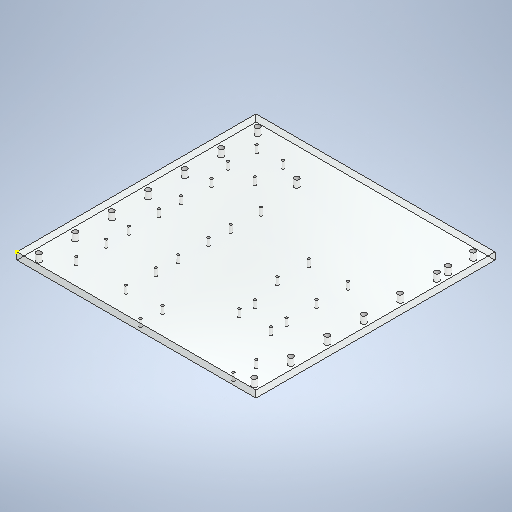
# Autodesk Inventor part: acrylic_base_2
Saved by Autodesk Inventor 2025.1 (Build 291241000, 241)
## iProperties
Created: 2026-09-08
Part Number: acrylic_base_2
Material: Generic
Document SubType Name: Modeling
Designer: Aiden
Density: 1 g/cm^3
Appearance: Default
Author: Aiden
Autodesk Inventor part; units mm, degrees
ref_plane "YZ Plane" through (0, 0, 0) normal (1, 0, 0) x (0, 1, 0)
ref_plane "XZ Plane" through (0, 0, 0) normal (0, 1, 0) x (-1, 0, 0)
ref_plane "XY Plane" through (0, 0, 0) normal (0, 0, 1) x (1, 0, 0)
sketch "Sketch1" plane through (0, 0, 0) normal (0, 1, 0) x (-1, 0, 0)
  line L0 (0, 0) -> (-304.8, 0)
  line L1 (-304.8, 0) -> (-304.8, -304.8)
  line L2 (-304.8, -304.8) -> (0, -304.8)
  line L3 (0, -304.8) -> (0, 0)
  dimension "d0" = 304.8
  dimension "d1" = 304.8
  constraints: 8 end point, 2 parallel, 1 horizontal, 1 perpendicular
  measures "d0" distance of L1.end L2.end
  measures "d1" distance of L2.end L0.start
extrude "Extrusion1" add sketch "Sketch1" along normal blind 9
sketch "Sketch3" plane through (0, 9, 0) normal (0, 1, 0) x (1, 0, 0)
  line L0 (304.8, 304.8) -> (0, 304.8) projected
  line L1 (152.4, 304.8) -> (152.4, 0) construction
  line L2 (0, 0) -> (304.8, 0) projected
  line L3 (0, 304.8) -> (0, 0) projected
  line L4 (0, 152.4) -> (304.8, 152.4) construction
  line L5 (304.8, 0) -> (304.8, 304.8) projected
  line L6 (289.8, 259.8) -> (96.8, 259.8) construction
  point P0 (289.8, 152.4)
  point P1 (289.8, 198.9)
  point P2 (289.8, 105.9)
  point P3 (289.8, 245.4)
  point P4 (289.8, 59.4)
  point P5 (289.8, 291.9)
  point P6 (289.8, 12.9)
  point P7 (15, 152.4)
  point P8 (15, 198.9)
  point P9 (15, 105.9)
  point P10 (15, 245.4)
  point P11 (15, 59.4)
  point P12 (15, 291.9)
  point P13 (15, 12.9)
  dimension "d20" = 193
  dimension "d38" = 46.5
  dimension "d43" = 45
  dimension "d44" = 15
  dimension "d45" = 15
  dimension "d46" = 12.9
  constraints: 7 symmetric about line, 6 end point, 4 midpoint, 1 coincident, 1 horizontal, 1 vertical, 6 other
  measures "d20" distance of L6.start L6.end
  measures "d38" distance of point (289.8, 152.4) point (289.8, 198.9)
  measures "d43" distance from line of L0 L6.start
  measures "d44" distance from line of L6.start L5
  measures "d45" distance from line of L5 point (289.8, 152.4)
  measures "d46" distance from line of point (289.8, 291.9) L0
hole "Hole1" at (289.8, 9, -152.4) at (96.8, 9, -259.8) at (289.8, 9, -259.8) at (15, 9, -291.9) at (15, 9, -245.4) at (15, 9, -198.9) at (15, 9, -152.4) at (15, 9, -105.9) at (15, 9, -59.4) at (15, 9, -12.9) at (289.8, 9, -291.9) at (289.8, 9, -245.4) at (289.8, 9, -105.9) at (289.8, 9, -59.4) at (289.8, 9, -12.9) at (289.8, 9, -198.9) direction (0, -1, 0) diameter 6.6 end through all
sketch "Sketch6" plane through (0, 9, 0) normal (0, 1, 0) x (1, 0, 0)
  point P0 (0, 0)
sketch "Sketch7" plane through (0, 9, 0) normal (0, 1, 0) x (1, 0, 0)
  arc A0 (105.2833, 206.7953) -> (105.2833, 203.5953) centre (105.2833, 205.1953) ccw projected
  line L0 (105.2833, 206.7953) -> (106.5833, 206.7953) projected
  arc A1 (106.5833, 203.5953) -> (106.5833, 206.7953) centre (106.5833, 205.1953) ccw projected
  line L1 (106.5833, 203.5953) -> (105.2833, 203.5953) projected
  arc A2 (106.5833, 165.1391) -> (106.5833, 168.3391) centre (106.5833, 166.7391) ccw projected
  line L2 (106.5833, 165.1391) -> (105.2833, 165.1391) projected
  arc A3 (105.2833, 168.3391) -> (105.2833, 165.1391) centre (105.2833, 166.7391) ccw projected
  line L3 (105.2833, 168.3391) -> (106.5833, 168.3391) projected
  arc A4 (43.3997, 165.1391) -> (43.3997, 168.3391) centre (43.3997, 166.7391) ccw projected
  line L4 (43.3997, 165.1391) -> (42.0997, 165.1391) projected
  arc A5 (42.0997, 168.3391) -> (42.0997, 165.1391) centre (42.0997, 166.7391) ccw projected
  line L5 (42.0997, 168.3391) -> (43.3997, 168.3391) projected
  line L6 (42.0997, 206.7953) -> (43.3997, 206.7953) projected
  arc A6 (43.3997, 203.5953) -> (43.3997, 206.7953) centre (43.3997, 205.1953) ccw projected
  line L7 (43.3997, 203.5953) -> (42.0997, 203.5953) projected
  arc A7 (42.0997, 206.7953) -> (42.0997, 203.5953) centre (42.0997, 205.1953) ccw projected
  spline S0 degree 3 poles (143.1833, 208.4353) (143.1833, 207.0944) (142.4879, 205.7761) (141.3875, 204.9942) (140.2562, 204.1904) (138.7283, 203.9647) (137.4066, 204.3999) (136.1385, 204.8174) (135.0844, 205.8385) (134.6567, 207.0914) (134.2262, 208.3527) (134.4508, 209.8128) (135.2354, 210.8939) (136.0421, 212.0056) (137.4107, 212.691) (138.7942, 212.6953) (138.7989, 212.6953) (138.8036, 212.6953) (138.8083, 212.6953) knots -3.141593 -3.141593 -3.141593 -3.141593 -2.205037 -2.205037 -2.205037 -1.242265 -1.242265 -1.242265 -0.318503 -0.318503 -0.318503 0.611382 0.611382 0.611382 1.567549 1.567549 1.567549 1.570796 1.570796 1.570796 1.570796 projected
  line L8 (9.8747, 212.6953) -> (138.8083, 212.6953) projected
  spline S1 degree 3 poles (9.8747, 212.6953) (11.2253, 212.6951) (12.5648, 212.0482) (13.3808, 210.9836) (13.938, 210.2568) (14.2497, 209.3479) (14.2497, 208.4353) knots 1.570796 1.570796 1.570796 1.570796 2.504243 2.504243 2.504243 3.141593 3.141593 3.141593 3.141593 projected
  spline S2 degree 3 poles (14.2497, 208.4353) (14.2497, 207.0944) (13.5543, 205.7761) (12.4539, 204.9942) (11.3226, 204.1904) (9.7947, 203.9647) (8.473, 204.3999) (7.2049, 204.8174) (6.1508, 205.8385) (5.7231, 207.0914) (5.5756, 207.5234) (5.505, 207.9788) (5.4997, 208.4353) knots -3.141593 -3.141593 -3.141593 -3.141593 -2.205037 -2.205037 -2.205037 -1.242265 -1.242265 -1.242265 -0.318503 -0.318503 -0.318503 0 0 0 0 projected
  line L9 (5.4997, 163.4991) -> (5.4997, 208.4353) projected
  spline S3 degree 3 poles (5.4997, 163.4991) (5.5121, 164.3722) (5.7859, 165.2469) (6.3018, 165.9577) (7.1085, 167.0694) (8.4771, 167.7548) (9.8606, 167.7591) (11.216, 167.7634) (12.5619, 167.1156) (13.3808, 166.0474) (13.938, 165.3206) (14.2497, 164.4117) (14.2497, 163.4991) knots 0 0 0 0 0.611382 0.611382 0.611382 1.567549 1.567549 1.567549 2.504243 2.504243 2.504243 3.141593 3.141593 3.141593 3.141593 projected
  spline S4 degree 3 poles (14.2497, 163.4991) (14.2497, 162.1582) (13.5543, 160.8399) (12.4539, 160.058) (11.7086, 159.5284) (10.7913, 159.2498) (9.8747, 159.2391) knots -3.141593 -3.141593 -3.141593 -3.141593 -2.205037 -2.205037 -2.205037 -1.570796 -1.570796 -1.570796 -1.570796 projected
  line L10 (138.8083, 159.2391) -> (9.8747, 159.2391) projected
  spline S5 degree 3 poles (138.8083, 159.2391) (138.3327, 159.2436) (137.8576, 159.3151) (137.4066, 159.4636) (136.1385, 159.8812) (135.0844, 160.9023) (134.6567, 162.1552) (134.2262, 163.4164) (134.4508, 164.8766) (135.2354, 165.9577) (136.0421, 167.0694) (137.4107, 167.7548) (138.7942, 167.7591) (140.1496, 167.7634) (141.4955, 167.1156) (142.3144, 166.0474) (142.8716, 165.3206) (143.1833, 164.4117) (143.1833, 163.4991) knots -1.570796 -1.570796 -1.570796 -1.570796 -1.242265 -1.242265 -1.242265 -0.318503 -0.318503 -0.318503 0.611382 0.611382 0.611382 1.567549 1.567549 1.567549 2.504243 2.504243 2.504243 3.141593 3.141593 3.141593 3.141593 projected
  line L11 (143.1833, 208.4353) -> (143.1833, 163.4991) projected
  arc A8 (105.2833, 139.7953) -> (105.2833, 136.5953) centre (105.2833, 138.1953) ccw projected
  line L12 (105.2833, 139.7953) -> (106.5833, 139.7953) projected
  arc A9 (106.5833, 136.5953) -> (106.5833, 139.7953) centre (106.5833, 138.1953) ccw projected
  line L13 (106.5833, 136.5953) -> (105.2833, 136.5953) projected
  arc A10 (106.5833, 98.1391) -> (106.5833, 101.3391) centre (106.5833, 99.7391) ccw projected
  line L14 (106.5833, 98.1391) -> (105.2833, 98.1391) projected
  arc A11 (105.2833, 101.3391) -> (105.2833, 98.1391) centre (105.2833, 99.7391) ccw projected
  line L15 (105.2833, 101.3391) -> (106.5833, 101.3391) projected
  arc A12 (43.3997, 98.1391) -> (43.3997, 101.3391) centre (43.3997, 99.7391) ccw projected
  line L16 (43.3997, 98.1391) -> (42.0997, 98.1391) projected
  arc A13 (42.0997, 101.3391) -> (42.0997, 98.1391) centre (42.0997, 99.7391) ccw projected
  line L17 (42.0997, 101.3391) -> (43.3997, 101.3391) projected
  line L18 (42.0997, 139.7953) -> (43.3997, 139.7953) projected
  arc A14 (43.3997, 136.5953) -> (43.3997, 139.7953) centre (43.3997, 138.1953) ccw projected
  line L19 (43.3997, 136.5953) -> (42.0997, 136.5953) projected
  arc A15 (42.0997, 139.7953) -> (42.0997, 136.5953) centre (42.0997, 138.1953) ccw projected
  spline S6 degree 3 poles (143.1833, 141.4353) (143.1833, 140.0944) (142.4879, 138.7761) (141.3875, 137.9942) (140.2562, 137.1904) (138.7283, 136.9647) (137.4066, 137.3999) (136.1385, 137.8174) (135.0844, 138.8385) (134.6567, 140.0914) (134.2262, 141.3527) (134.4508, 142.8128) (135.2354, 143.8939) (136.0421, 145.0056) (137.4107, 145.691) (138.7942, 145.6953) (138.7989, 145.6953) (138.8036, 145.6953) (138.8083, 145.6953) knots -3.141593 -3.141593 -3.141593 -3.141593 -2.205037 -2.205037 -2.205037 -1.242265 -1.242265 -1.242265 -0.318503 -0.318503 -0.318503 0.611382 0.611382 0.611382 1.567549 1.567549 1.567549 1.570796 1.570796 1.570796 1.570796 projected
  line L20 (9.8747, 145.6953) -> (138.8083, 145.6953) projected
  spline S7 degree 3 poles (9.8747, 145.6953) (11.2253, 145.6951) (12.5648, 145.0482) (13.3808, 143.9836) (13.938, 143.2568) (14.2497, 142.3479) (14.2497, 141.4353) knots 1.570796 1.570796 1.570796 1.570796 2.504243 2.504243 2.504243 3.141593 3.141593 3.141593 3.141593 projected
  spline S8 degree 3 poles (14.2497, 141.4353) (14.2497, 140.0944) (13.5543, 138.7761) (12.4539, 137.9942) (11.3226, 137.1904) (9.7947, 136.9647) (8.473, 137.3999) (7.2049, 137.8174) (6.1508, 138.8385) (5.7231, 140.0914) (5.5756, 140.5234) (5.505, 140.9788) (5.4997, 141.4353) knots -3.141593 -3.141593 -3.141593 -3.141593 -2.205037 -2.205037 -2.205037 -1.242265 -1.242265 -1.242265 -0.318503 -0.318503 -0.318503 0 0 0 0 projected
  line L21 (5.4997, 96.4991) -> (5.4997, 141.4353) projected
  spline S9 degree 3 poles (5.4997, 96.4991) (5.5121, 97.3722) (5.7859, 98.2469) (6.3018, 98.9577) (7.1085, 100.0694) (8.4771, 100.7548) (9.8606, 100.7591) (11.216, 100.7634) (12.5619, 100.1156) (13.3808, 99.0474) (13.938, 98.3206) (14.2497, 97.4117) (14.2497, 96.4991) knots 0 0 0 0 0.611382 0.611382 0.611382 1.567549 1.567549 1.567549 2.504243 2.504243 2.504243 3.141593 3.141593 3.141593 3.141593 projected
  spline S10 degree 3 poles (14.2497, 96.4991) (14.2497, 95.1582) (13.5543, 93.8399) (12.4539, 93.058) (11.7086, 92.5284) (10.7913, 92.2498) (9.8747, 92.2391) knots -3.141593 -3.141593 -3.141593 -3.141593 -2.205037 -2.205037 -2.205037 -1.570796 -1.570796 -1.570796 -1.570796 projected
  line L22 (138.8083, 92.2391) -> (9.8747, 92.2391) projected
  spline S11 degree 3 poles (138.8083, 92.2391) (138.3327, 92.2436) (137.8576, 92.3151) (137.4066, 92.4636) (136.1385, 92.8812) (135.0844, 93.9023) (134.6567, 95.1552) (134.2262, 96.4164) (134.4508, 97.8766) (135.2354, 98.9577) (136.0421, 100.0694) (137.4107, 100.7548) (138.7942, 100.7591) (140.1496, 100.7634) (141.4955, 100.1156) (142.3144, 99.0474) (142.8716, 98.3206) (143.1833, 97.4117) (143.1833, 96.4991) knots -1.570796 -1.570796 -1.570796 -1.570796 -1.242265 -1.242265 -1.242265 -0.318503 -0.318503 -0.318503 0.611382 0.611382 0.611382 1.567549 1.567549 1.567549 2.504243 2.504243 2.504243 3.141593 3.141593 3.141593 3.141593 projected
  line L23 (143.1833, 141.4353) -> (143.1833, 96.4991) projected
  arc A16 (105.2833, 72.7953) -> (105.2833, 69.5953) centre (105.2833, 71.1953) ccw projected
  line L24 (105.2833, 72.7953) -> (106.5833, 72.7953) projected
  arc A17 (106.5833, 69.5953) -> (106.5833, 72.7953) centre (106.5833, 71.1953) ccw projected
  line L25 (106.5833, 69.5953) -> (105.2833, 69.5953) projected
  arc A18 (106.5833, 31.1391) -> (106.5833, 34.3391) centre (106.5833, 32.7391) ccw projected
  line L26 (106.5833, 31.1391) -> (105.2833, 31.1391) projected
  arc A19 (105.2833, 34.3391) -> (105.2833, 31.1391) centre (105.2833, 32.7391) ccw projected
  line L27 (105.2833, 34.3391) -> (106.5833, 34.3391) projected
  arc A20 (43.3997, 31.1391) -> (43.3997, 34.3391) centre (43.3997, 32.7391) ccw projected
  line L28 (43.3997, 31.1391) -> (42.0997, 31.1391) projected
  arc A21 (42.0997, 34.3391) -> (42.0997, 31.1391) centre (42.0997, 32.7391) ccw projected
  line L29 (42.0997, 34.3391) -> (43.3997, 34.3391) projected
  line L30 (42.0997, 72.7953) -> (43.3997, 72.7953) projected
  arc A22 (43.3997, 69.5953) -> (43.3997, 72.7953) centre (43.3997, 71.1953) ccw projected
  line L31 (43.3997, 69.5953) -> (42.0997, 69.5953) projected
  arc A23 (42.0997, 72.7953) -> (42.0997, 69.5953) centre (42.0997, 71.1953) ccw projected
  spline S12 degree 3 poles (143.1833, 74.4353) (143.1833, 73.0944) (142.4879, 71.7761) (141.3875, 70.9942) (140.2562, 70.1904) (138.7283, 69.9647) (137.4066, 70.3999) (136.1385, 70.8174) (135.0844, 71.8385) (134.6567, 73.0914) (134.2262, 74.3527) (134.4508, 75.8128) (135.2354, 76.8939) (136.0421, 78.0056) (137.4107, 78.691) (138.7942, 78.6953) (138.7989, 78.6953) (138.8036, 78.6953) (138.8083, 78.6953) knots -3.141593 -3.141593 -3.141593 -3.141593 -2.205037 -2.205037 -2.205037 -1.242265 -1.242265 -1.242265 -0.318503 -0.318503 -0.318503 0.611382 0.611382 0.611382 1.567549 1.567549 1.567549 1.570796 1.570796 1.570796 1.570796 projected
  line L32 (9.8747, 78.6953) -> (138.8083, 78.6953) projected
  spline S13 degree 3 poles (9.8747, 78.6953) (11.2253, 78.6951) (12.5648, 78.0482) (13.3808, 76.9836) (13.938, 76.2568) (14.2497, 75.3479) (14.2497, 74.4353) knots 1.570796 1.570796 1.570796 1.570796 2.504243 2.504243 2.504243 3.141593 3.141593 3.141593 3.141593 projected
  spline S14 degree 3 poles (14.2497, 74.4353) (14.2497, 73.0944) (13.5543, 71.7761) (12.4539, 70.9942) (11.3226, 70.1904) (9.7947, 69.9647) (8.473, 70.3999) (7.2049, 70.8174) (6.1508, 71.8385) (5.7231, 73.0914) (5.5756, 73.5234) (5.505, 73.9788) (5.4997, 74.4353) knots -3.141593 -3.141593 -3.141593 -3.141593 -2.205037 -2.205037 -2.205037 -1.242265 -1.242265 -1.242265 -0.318503 -0.318503 -0.318503 0 0 0 0 projected
  line L33 (5.4997, 29.4991) -> (5.4997, 74.4353) projected
  spline S15 degree 3 poles (5.4997, 29.4991) (5.5121, 30.3722) (5.7859, 31.2469) (6.3018, 31.9577) (7.1085, 33.0694) (8.4771, 33.7548) (9.8606, 33.7591) (11.216, 33.7634) (12.5619, 33.1156) (13.3808, 32.0474) (13.938, 31.3206) (14.2497, 30.4117) (14.2497, 29.4991) knots 0 0 0 0 0.611382 0.611382 0.611382 1.567549 1.567549 1.567549 2.504243 2.504243 2.504243 3.141593 3.141593 3.141593 3.141593 projected
  spline S16 degree 3 poles (14.2497, 29.4991) (14.2497, 28.1582) (13.5543, 26.8399) (12.4539, 26.058) (11.7086, 25.5284) (10.7913, 25.2498) (9.8747, 25.2391) knots -3.141593 -3.141593 -3.141593 -3.141593 -2.205037 -2.205037 -2.205037 -1.570796 -1.570796 -1.570796 -1.570796 projected
  line L34 (138.8083, 25.2391) -> (9.8747, 25.2391) projected
  spline S17 degree 3 poles (138.8083, 25.2391) (138.3327, 25.2436) (137.8576, 25.3151) (137.4066, 25.4636) (136.1385, 25.8812) (135.0844, 26.9023) (134.6567, 28.1552) (134.2262, 29.4164) (134.4508, 30.8766) (135.2354, 31.9577) (136.0421, 33.0694) (137.4107, 33.7548) (138.7942, 33.7591) (140.1496, 33.7634) (141.4955, 33.1156) (142.3144, 32.0474) (142.8716, 31.3206) (143.1833, 30.4117) (143.1833, 29.4991) knots -1.570796 -1.570796 -1.570796 -1.570796 -1.242265 -1.242265 -1.242265 -0.318503 -0.318503 -0.318503 0.611382 0.611382 0.611382 1.567549 1.567549 1.567549 2.504243 2.504243 2.504243 3.141593 3.141593 3.141593 3.141593 projected
  line L35 (143.1833, 74.4353) -> (143.1833, 29.4991) projected
  line L36 (67.8539, 272.6632) -> (69.1539, 272.6637) projected
  arc A24 (69.1553, 269.4637) -> (69.1539, 272.6637) centre (69.1546, 271.0637) ccw projected
  line L37 (69.1553, 269.4637) -> (67.8553, 269.4632) projected
  arc A25 (67.8539, 272.6632) -> (67.8553, 269.4632) centre (67.8546, 271.0632) ccw projected
  arc A26 (67.87, 236.3632) -> (67.8714, 233.1632) centre (67.8707, 234.7632) ccw projected
  line L38 (67.87, 236.3632) -> (69.17, 236.3637) projected
  arc A27 (69.1714, 233.1637) -> (69.17, 236.3637) centre (69.1707, 234.7637) ccw projected
  line L39 (69.1714, 233.1637) -> (67.8714, 233.1632) projected
  arc A28 (33.8664, 272.6481) -> (33.8678, 269.4481) centre (33.8671, 271.0481) ccw projected
  line L40 (33.8664, 272.6481) -> (35.1664, 272.6486) projected
  arc A29 (35.1678, 269.4486) -> (35.1664, 272.6486) centre (35.1671, 271.0486) ccw projected
  line L41 (35.1678, 269.4486) -> (33.8678, 269.4481) projected
  line L42 (33.8825, 236.3481) -> (35.1825, 236.3486) projected
  arc A30 (35.1839, 233.1486) -> (35.1825, 236.3486) centre (35.1832, 234.7486) ccw projected
  line L43 (35.1839, 233.1486) -> (33.8839, 233.1481) projected
  arc A31 (33.8825, 236.3481) -> (33.8839, 233.1481) centre (33.8832, 234.7481) ccw projected
  arc A32 (17.2653, 275.1407) -> (21.2635, 279.1425) centre (21.2653, 275.1425) ccw projected
  line L44 (17.285, 230.6407) -> (17.2653, 275.1407) projected
  arc A33 (21.2868, 226.6425) -> (17.285, 230.6407) centre (21.285, 230.6425) ccw projected
  line L45 (81.7743, 226.6693) -> (21.2868, 226.6425) projected
  arc A34 (81.7743, 226.6693) -> (85.7725, 230.6711) centre (81.7725, 230.6693) ccw projected
  line L46 (85.7627, 252.9211) -> (85.7725, 230.6711) projected
  circle A35 centre (81.7627, 252.9193) radius 4 projected
  line L47 (85.7528, 275.1711) -> (85.7627, 252.9211) projected
  arc A36 (85.7528, 275.1711) -> (81.751, 279.1693) centre (81.7528, 275.1693) ccw projected
  line L48 (21.2635, 279.1425) -> (81.751, 279.1693) projected
  arc A37 (194.1246, 137.0569) -> (194.1232, 140.2569) centre (194.1239, 138.6569) ccw projected
  line L49 (194.1246, 137.0569) -> (192.8246, 137.0563) projected
  arc A38 (192.8232, 140.2563) -> (192.8246, 137.0563) centre (192.8239, 138.6563) ccw projected
  line L50 (192.8232, 140.2563) -> (194.1232, 140.2569) projected
  line L51 (194.1069, 177.0569) -> (192.8069, 177.0563) projected
  arc A39 (192.8054, 180.2563) -> (192.8069, 177.0563) centre (192.8061, 178.6563) ccw projected
  line L52 (192.8054, 180.2563) -> (194.1054, 180.2569) projected
  arc A40 (194.1069, 177.0569) -> (194.1054, 180.2569) centre (194.1061, 178.6569) ccw projected
  arc A41 (242.8054, 180.2785) -> (242.8069, 177.0785) centre (242.8061, 178.6785) ccw projected
  line L53 (242.8054, 180.2785) -> (244.1054, 180.2791) projected
  arc A42 (244.1069, 177.0791) -> (244.1054, 180.2791) centre (244.1061, 178.6791) ccw projected
  line L54 (244.1069, 177.0791) -> (242.8069, 177.0785) projected
  line L55 (244.1246, 137.0791) -> (242.8246, 137.0785) projected
  arc A43 (242.8232, 140.2785) -> (242.8246, 137.0785) centre (242.8239, 138.6785) ccw projected
  line L56 (242.8232, 140.2785) -> (244.1232, 140.2791) projected
  arc A44 (244.1246, 137.0791) -> (244.1232, 140.2791) centre (244.1239, 138.6791) ccw projected
  arc A45 (259.7525, 186.7861) -> (263.7543, 182.7878) centre (259.7543, 182.7861) ccw projected
  line L57 (177.1525, 186.7494) -> (259.7525, 186.7861) projected
  arc A46 (173.1543, 182.7476) -> (177.1525, 186.7494) centre (177.1543, 182.7494) ccw projected
  line L58 (173.1723, 142.2266) -> (173.1543, 182.7476) projected
  arc A47 (173.1723, 142.2266) -> (182.8567, 130.6174) centre (184.9791, 142.2318) ccw projected
  arc A48 (183.5775, 130.5522) -> (182.8567, 130.6174) centre (183.5757, 134.5522) ccw projected
  line L59 (258.4775, 130.5855) -> (183.5775, 130.5522) projected
  circle A49 centre (258.4757, 134.5855) radius 4 projected
  arc A50 (258.4775, 130.5855) -> (263.7752, 135.8878) centre (258.4752, 135.8855) ccw projected
  line L60 (263.7543, 182.7878) -> (263.7752, 135.8878) projected
  line L61 (203.8113, 100.5945) -> (205.3113, 100.5952) projected
  arc A51 (205.3126, 97.5952) -> (205.3113, 100.5952) centre (205.3119, 99.0952) ccw projected
  line L62 (205.3126, 97.5952) -> (203.8126, 97.5945) projected
  arc A52 (203.8113, 100.5945) -> (203.8126, 97.5945) centre (203.8119, 99.0945) ccw projected
  arc A53 (245.3126, 97.613) -> (245.3113, 100.613) centre (245.3119, 99.113) ccw projected
  line L63 (245.3126, 97.613) -> (243.8126, 97.6123) projected
  arc A54 (243.8113, 100.6123) -> (243.8126, 97.6123) centre (243.8119, 99.1123) ccw projected
  line L64 (243.8113, 100.6123) -> (245.3113, 100.613) projected
  arc A55 (203.8202, 80.5945) -> (203.8215, 77.5945) centre (203.8208, 79.0945) ccw projected
  line L65 (203.8202, 80.5945) -> (205.3202, 80.5952) projected
  arc A56 (205.3215, 77.5952) -> (205.3202, 80.5952) centre (205.3208, 79.0952) ccw projected
  line L66 (205.3215, 77.5952) -> (203.8215, 77.5945) projected
  arc A57 (245.3215, 77.613) -> (245.3202, 80.613) centre (245.3208, 79.113) ccw projected
  line L67 (245.3215, 77.613) -> (243.8215, 77.6123) projected
  arc A58 (243.8202, 80.6123) -> (243.8215, 77.6123) centre (243.8208, 79.1123) ccw projected
  line L68 (243.8202, 80.6123) -> (245.3202, 80.613) projected
  arc A59 (189.5677, 108.7282) -> (193.5659, 112.73) centre (193.5677, 108.73) ccw projected
  line L69 (189.5851, 69.4482) -> (189.5677, 108.7282) projected
  arc A60 (193.5869, 65.45) -> (189.5851, 69.4482) centre (193.5851, 69.45) ccw projected
  line L70 (255.5669, 65.4775) -> (193.5869, 65.45) projected
  arc A61 (259.5651, 69.4793) -> (255.5669, 65.4775) centre (255.5651, 69.4775) ccw projected
  line L71 (259.5477, 108.7593) -> (259.5651, 69.4793) projected
  arc A62 (255.5459, 112.7575) -> (259.5477, 108.7593) centre (255.5477, 108.7575) ccw projected
  line L72 (193.5659, 112.73) -> (255.5459, 112.7575) projected
  line L73 (257.7433, 34.6845) -> (165.5439, 34.6845) projected
  line L74 (163.4226, 36.1845) -> (165.5439, 34.6845) projected
  line L75 (163.4226, 36.1845) -> (155.4226, 36.1845) projected
  line L76 (155.4226, 36.1845) -> (155.4226, 1.9425) projected
  line L77 (163.4226, 1.9425) -> (155.4226, 1.9425) projected
  line L78 (165.5439, 3.4425) -> (163.4226, 1.9425) projected
  line L79 (165.5439, 3.4425) -> (257.7433, 3.4425) projected
  line L80 (259.8646, 1.9425) -> (257.7433, 3.4425) projected
  line L81 (267.8646, 1.9425) -> (259.8646, 1.9425) projected
  line L82 (267.8646, 1.9425) -> (267.8646, 36.1845) projected
  line L83 (267.8646, 36.1845) -> (259.8646, 36.1845) projected
  line L84 (257.7433, 34.6845) -> (259.8646, 36.1845) projected
  circle A63 centre (152.4563, 5.1939) radius 1.6 projected
  circle A64 centre (152.0432, 33.7339) radius 1.6 projected
  line L85 (155.4226, 36.1845) -> (155.4226, 22.4685) projected
  line L86 (149.4226, 36.1845) -> (155.4226, 36.1845) projected
  line L87 (149.4226, 1.9425) -> (149.4226, 36.1845) projected
  line L88 (155.4226, 1.9425) -> (149.4226, 1.9425) projected
  line L89 (155.4226, 15.6585) -> (155.4226, 1.9425) projected
  line L90 (155.4226, 22.4685) -> (155.4226, 15.6585) projected
  circle A65 centre (270.8309, 5.1939) radius 1.6 projected
  circle A66 centre (271.244, 33.7339) radius 1.6 projected
  line L91 (267.8646, 1.9425) -> (267.8646, 36.1845) projected
  line L92 (267.8646, 1.9425) -> (273.8646, 1.9425) projected
  line L93 (273.8646, 1.9425) -> (273.8646, 36.1845) projected
  line L94 (273.8646, 36.1845) -> (267.8646, 36.1845) projected
  line L95 (33.8671, 271.0481) -> (35.1671, 271.0486)
  line L96 (67.8546, 271.0632) -> (69.1546, 271.0637)
  line L97 (67.8707, 234.7632) -> (69.1707, 234.7637)
  line L98 (33.8832, 234.7481) -> (35.1832, 234.7486)
  line L99 (42.0997, 205.1953) -> (43.3997, 205.1953)
  line L100 (105.2833, 205.1953) -> (106.5833, 205.1953)
  line L101 (105.2833, 166.7391) -> (106.5833, 166.7391)
  line L102 (42.0997, 166.7391) -> (43.3997, 166.7391)
  arc A67 (194.1246, 137.0569) -> (194.1232, 140.2569) centre (194.1239, 138.6569) ccw projected
  line L103 (194.1246, 137.0569) -> (192.8246, 137.0563) projected
  arc A68 (192.8232, 140.2563) -> (192.8246, 137.0563) centre (192.8239, 138.6563) ccw projected
  line L104 (192.8232, 140.2563) -> (194.1232, 140.2569) projected
  line L105 (194.1069, 177.0569) -> (192.8069, 177.0563) projected
  arc A69 (192.8054, 180.2563) -> (192.8069, 177.0563) centre (192.8061, 178.6563) ccw projected
  line L106 (192.8054, 180.2563) -> (194.1054, 180.2569) projected
  arc A70 (194.1069, 177.0569) -> (194.1054, 180.2569) centre (194.1061, 178.6569) ccw projected
  arc A71 (242.8054, 180.2785) -> (242.8069, 177.0785) centre (242.8061, 178.6785) ccw projected
  line L107 (242.8054, 180.2785) -> (244.1054, 180.2791) projected
  arc A72 (244.1069, 177.0791) -> (244.1054, 180.2791) centre (244.1061, 178.6791) ccw projected
  line L108 (244.1069, 177.0791) -> (242.8069, 177.0785) projected
  line L109 (244.1246, 137.0791) -> (242.8246, 137.0785) projected
  arc A73 (242.8232, 140.2785) -> (242.8246, 137.0785) centre (242.8239, 138.6785) ccw projected
  line L110 (242.8232, 140.2785) -> (244.1232, 140.2791) projected
  arc A74 (244.1246, 137.0791) -> (244.1232, 140.2791) centre (244.1239, 138.6791) ccw projected
  arc A75 (259.7525, 186.7861) -> (263.7543, 182.7878) centre (259.7543, 182.7861) ccw projected
  line L111 (177.1525, 186.7494) -> (259.7525, 186.7861) projected
  arc A76 (173.1543, 182.7476) -> (177.1525, 186.7494) centre (177.1543, 182.7494) ccw projected
  line L112 (173.1723, 142.2266) -> (173.1543, 182.7476) projected
  arc A77 (173.1723, 142.2266) -> (182.8567, 130.6174) centre (184.9791, 142.2318) ccw projected
  arc A78 (183.5775, 130.5522) -> (182.8567, 130.6174) centre (183.5757, 134.5522) ccw projected
  line L113 (258.4775, 130.5855) -> (183.5775, 130.5522) projected
  circle A79 centre (258.4757, 134.5855) radius 4 projected
  arc A80 (258.4775, 130.5855) -> (263.7752, 135.8878) centre (258.4752, 135.8855) ccw projected
  line L114 (263.7543, 182.7878) -> (263.7752, 135.8878) projected
  line L115 (105.2833, 71.1953) -> (106.5833, 71.1953)
  line L116 (42.0997, 138.1953) -> (43.3997, 138.1953)
  line L117 (105.2833, 138.1953) -> (106.5833, 138.1953)
  line L118 (105.2833, 99.7391) -> (106.5833, 99.7391)
  line L119 (42.0997, 99.7391) -> (43.3997, 99.7391)
  line L120 (42.0997, 71.1953) -> (43.3997, 71.1953)
  line L121 (105.2833, 32.7391) -> (106.5833, 32.7391)
  line L122 (42.0997, 32.7391) -> (43.3997, 32.7391)
  point P0 (0, 0)
  point P1 (42.7497, 138.1953)
  point P2 (105.9333, 138.1953)
  point P3 (105.9333, 99.7391)
  point P4 (42.7497, 99.7391)
  point P5 (42.7497, 71.1953)
  point P6 (105.9333, 71.1953)
  point P7 (105.9333, 32.7391)
  point P8 (42.7497, 32.7391)
  point P9 (204.5715, 99.1116)
  point P10 (244.5702, 99.1116)
  point P11 (244.5702, 79.1116)
  point P12 (204.5626, 79.0952)
  point P13 (193.4561, 178.6566)
  point P14 (243.4561, 178.6788)
  point P15 (243.4739, 138.6788)
  point P16 (193.4739, 138.6566)
  point P17 (193.4561, 178.6566)
  point P18 (193.4739, 138.6566)
  point P19 (193.4561, 178.6566)
  point P20 (243.4561, 178.6788)
  point P21 (243.4739, 138.6788)
  point P22 (105.9333, 205.1953)
  point P23 (42.7497, 205.1953)
  point P24 (42.7497, 166.7391)
  point P25 (105.9333, 166.7391)
  point P26 (68.5207, 234.7635)
  point P27 (34.5332, 234.7484)
  point P28 (34.5171, 271.0484)
  point P29 (68.5046, 271.0635)
  constraints: 32 end point, 16 midpoint, 12 horizontal, 9 coincident, 2 horizontal alignment, 3 other
hole "Hole3" at (42.7497, 9, -166.7391) at (105.9333, 9, -166.7391) at (105.9333, 9, -205.1953) at (42.7497, 9, -205.1953) at (34.5332, 9, -234.7484) at (68.5207, 9, -234.7635) at (68.5046, 9, -271.0635) at (34.5171, 9, -271.0484) at (42.7497, 9, -138.1953) at (105.9333, 9, -138.1953) at (105.9333, 9, -99.7391) at (42.7497, 9, -99.7391) at (42.7497, 9, -32.7391) at (42.7497, 9, -71.1953) at (105.9333, 9, -71.1953) at (105.9333, 9, -32.7391) at (152.0432, 9, -33.7339) at (152.4563, 9, -5.1939) at (271.244, 9, -33.7339) at (270.8309, 9, -5.1939) at (244.5702, 9, -79.1116) at (204.5715, 9, -99.1116) at (244.5702, 9, -99.1116) at (204.5626, 9, -79.0952) at (193.4739, 9, -138.6566) at (243.4739, 9, -138.6788) at (243.4561, 9, -178.6788) at (193.4561, 9, -178.6566) direction (0, -1, 0) diameter 3.2 end through all
sketch "Sketch4" plane through (0, 9, 0) normal (0, 1, 0) x (1, 0, 0)
  line L0 (0, 304.8) -> (0, 0) projected
  line L1 (0, 0) -> (304.8, 0) projected
  line L2 (0, 304.8) -> (0, 0) projected
  line L3 (0, 152.4) -> (304.8, 152.4) construction
  line L4 (304.8, 0) -> (304.8, 304.8) projected
  circle A0 centre (289.8, 12.9) radius 3.3 projected
  circle A1 centre (15, 12.9) radius 3.3 projected
  line L5 (15, 12.9) -> (289.8, 12.9) construction
  circle A2 centre (289.8, 152.4) radius 3.3 projected
  line L6 (289.8, 152.4) -> (289.8, 12.9) construction
  line L7 (304.8, 304.8) -> (0, 304.8) projected
  circle A3 centre (15, 291.9) radius 3.3 projected
  line L8 (15, 291.9) -> (289.8, 291.9)
  line L9 (289.8, 291.9) -> (289.8, 12.9)
  line L10 (15, 12.9) -> (289.8, 12.9)
  line L11 (15, 291.9) -> (15, 12.9)
  point P0 (152.4, 152.4)
  point P1 (152.4, 152.4)
  point P2 (15, 288.6)
  point P3 (15, 16.2)
  point P4 (18.3, 12.9)
  point P5 (286.5, 12.9)
  point P6 (289.8, 16.2)
  point P7 (289.8, 149.1)
  point P8 (289.8, 155.7)
  point P9 (18.3, 291.9)
  point P10 (268.65, 12.9)
  point P11 (247.5, 12.9)
  point P12 (226.35, 12.9)
  point P13 (205.2, 12.9)
  point P14 (184.05, 12.9)
  point P15 (162.9, 12.9)
  point P16 (141.75, 12.9)
  point P17 (120.6, 12.9)
  point P18 (99.45, 12.9)
  point P19 (78.3, 12.9)
  point P20 (57.15, 12.9)
  point P21 (36, 12.9)
  point P22 (14.85, 12.9)
  point P23 (289.8, 34.35)
  point P24 (268.65, 34.35)
  point P25 (247.5, 34.35)
  point P26 (226.35, 34.35)
  point P27 (205.2, 34.35)
  point P28 (184.05, 34.35)
  point P29 (162.9, 34.35)
  point P30 (141.75, 34.35)
  point P31 (120.6, 34.35)
  point P32 (99.45, 34.35)
  point P33 (78.3, 34.35)
  point P34 (57.15, 34.35)
  point P35 (36, 34.35)
  point P36 (14.85, 34.35)
  point P37 (289.8, 55.8)
  point P38 (268.65, 55.8)
  point P39 (247.5, 55.8)
  point P40 (226.35, 55.8)
  point P41 (205.2, 55.8)
  point P42 (184.05, 55.8)
  point P43 (162.9, 55.8)
  point P44 (141.75, 55.8)
  point P45 (120.6, 55.8)
  point P46 (99.45, 55.8)
  point P47 (78.3, 55.8)
  point P48 (57.15, 55.8)
  point P49 (36, 55.8)
  point P50 (14.85, 55.8)
  point P51 (289.8, 77.25)
  point P52 (268.65, 77.25)
  point P53 (247.5, 77.25)
  point P54 (226.35, 77.25)
  point P55 (205.2, 77.25)
  point P56 (184.05, 77.25)
  point P57 (162.9, 77.25)
  point P58 (141.75, 77.25)
  point P59 (120.6, 77.25)
  point P60 (99.45, 77.25)
  point P61 (78.3, 77.25)
  point P62 (57.15, 77.25)
  point P63 (36, 77.25)
  point P64 (14.85, 77.25)
  point P65 (289.8, 98.7)
  point P66 (268.65, 98.7)
  point P67 (247.5, 98.7)
  point P68 (226.35, 98.7)
  point P69 (205.2, 98.7)
  point P70 (184.05, 98.7)
  point P71 (162.9, 98.7)
  point P72 (141.75, 98.7)
  point P73 (120.6, 98.7)
  point P74 (99.45, 98.7)
  point P75 (78.3, 98.7)
  point P76 (57.15, 98.7)
  point P77 (36, 98.7)
  point P78 (14.85, 98.7)
  point P79 (289.8, 120.15)
  point P80 (268.65, 120.15)
  point P81 (247.5, 120.15)
  point P82 (226.35, 120.15)
  point P83 (205.2, 120.15)
  point P84 (184.05, 120.15)
  point P85 (162.9, 120.15)
  point P86 (141.75, 120.15)
  point P87 (120.6, 120.15)
  point P88 (99.45, 120.15)
  point P89 (78.3, 120.15)
  point P90 (57.15, 120.15)
  point P91 (36, 120.15)
  point P92 (14.85, 120.15)
  point P93 (289.8, 141.6)
  point P94 (268.65, 141.6)
  point P95 (247.5, 141.6)
  point P96 (226.35, 141.6)
  point P97 (205.2, 141.6)
  point P98 (184.05, 141.6)
  point P99 (162.9, 141.6)
  point P100 (141.75, 141.6)
  point P101 (120.6, 141.6)
  point P102 (99.45, 141.6)
  point P103 (78.3, 141.6)
  point P104 (57.15, 141.6)
  point P105 (36, 141.6)
  point P106 (14.85, 141.6)
  point P107 (289.8, 163.05)
  point P108 (268.65, 163.05)
  point P109 (247.5, 163.05)
  point P110 (226.35, 163.05)
  point P111 (205.2, 163.05)
  point P112 (184.05, 163.05)
  point P113 (162.9, 163.05)
  point P114 (141.75, 163.05)
  point P115 (120.6, 163.05)
  point P116 (99.45, 163.05)
  point P117 (78.3, 163.05)
  point P118 (57.15, 163.05)
  point P119 (36, 163.05)
  point P120 (14.85, 163.05)
  point P121 (289.8, 184.5)
  point P122 (268.65, 184.5)
  point P123 (247.5, 184.5)
  point P124 (226.35, 184.5)
  point P125 (205.2, 184.5)
  point P126 (184.05, 184.5)
  point P127 (162.9, 184.5)
  point P128 (141.75, 184.5)
  point P129 (120.6, 184.5)
  point P130 (99.45, 184.5)
  point P131 (78.3, 184.5)
  point P132 (57.15, 184.5)
  point P133 (36, 184.5)
  point P134 (14.85, 184.5)
  point P135 (289.8, 205.95)
  point P136 (268.65, 205.95)
  point P137 (247.5, 205.95)
  point P138 (226.35, 205.95)
  point P139 (205.2, 205.95)
  point P140 (184.05, 205.95)
  point P141 (162.9, 205.95)
  point P142 (141.75, 205.95)
  point P143 (120.6, 205.95)
  point P144 (99.45, 205.95)
  point P145 (78.3, 205.95)
  point P146 (57.15, 205.95)
  point P147 (36, 205.95)
  point P148 (14.85, 205.95)
  point P149 (289.8, 227.4)
  point P150 (268.65, 227.4)
  point P151 (247.5, 227.4)
  point P152 (226.35, 227.4)
  point P153 (205.2, 227.4)
  point P154 (184.05, 227.4)
  point P155 (162.9, 227.4)
  point P156 (141.75, 227.4)
  point P157 (120.6, 227.4)
  point P158 (99.45, 227.4)
  point P159 (78.3, 227.4)
  point P160 (57.15, 227.4)
  point P161 (36, 227.4)
  point P162 (14.85, 227.4)
  point P163 (289.8, 248.85)
  point P164 (268.65, 248.85)
  point P165 (247.5, 248.85)
  point P166 (226.35, 248.85)
  point P167 (205.2, 248.85)
  point P168 (184.05, 248.85)
  point P169 (162.9, 248.85)
  point P170 (141.75, 248.85)
  point P171 (120.6, 248.85)
  point P172 (99.45, 248.85)
  point P173 (78.3, 248.85)
  point P174 (57.15, 248.85)
  point P175 (36, 248.85)
  point P176 (14.85, 248.85)
  point P177 (289.8, 270.3)
  point P178 (268.65, 270.3)
  point P179 (247.5, 270.3)
  point P180 (226.35, 270.3)
  point P181 (205.2, 270.3)
  point P182 (184.05, 270.3)
  point P183 (162.9, 270.3)
  point P184 (141.75, 270.3)
  point P185 (120.6, 270.3)
  point P186 (99.45, 270.3)
  point P187 (78.3, 270.3)
  point P188 (57.15, 270.3)
  point P189 (36, 270.3)
  point P190 (14.85, 270.3)
  point P191 (289.8, 291.75)
  point P192 (268.65, 291.75)
  point P193 (247.5, 291.75)
  point P194 (226.35, 291.75)
  point P195 (205.2, 291.75)
  point P196 (184.05, 291.75)
  point P197 (162.9, 291.75)
  point P198 (141.75, 291.75)
  point P199 (120.6, 291.75)
  dimension "d69" = 21.15
  dimension "d72" = 21.45
  dimension "d76" = 21.45
  dimension "d77" = 21.15
  constraints: 14 end point, 4 perpendicular, 3 horizontal, 3 midpoint, 2 coincident, 1 vertical, 195 other
  measures "d76" distance of A0.centre A2.centre
  measures "d77" distance of A1.centre A0.centre
body "Solid1"
